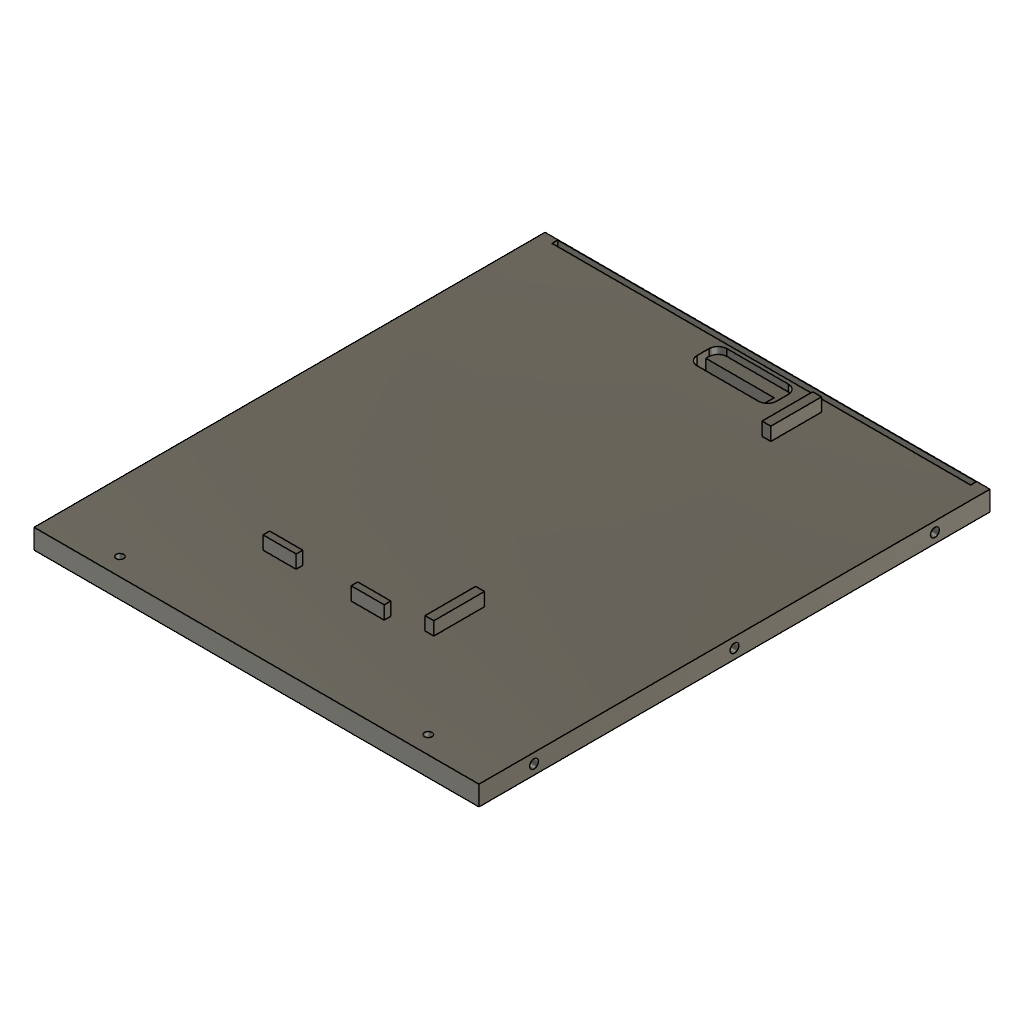
Base (Autodesk Fusion 360 design; units mm, degrees)
part number: 2026-10-19-10-28-36-439
Autodesk Fusion 360 part; units mm, degrees
sketch "plate" plane through (0, 0, 0) normal (0, 0, 1) x (1, 0, 0)
  line L0 (-101, 0) -> (101, 0)
  line L1 (101, 0) -> (101, 232)
  line L2 (101, 232) -> (-101, 232)
  line L3 (-101, 232) -> (-101, 0)
extrude "plate (1)" add sketch "plate" along normal blind 3 from surface at 6
sketch "rib_L" plane through (0, 0, 0) normal (0, 0, 1) x (1, 0, 0)
  line L0 (-101, 0) -> (-91, 0)
  line L1 (-91, 0) -> (-91, 232)
  line L2 (-91, 232) -> (-101, 232)
  line L3 (-101, 232) -> (-101, 0)
extrude "rib_L (1)" add sketch "rib_L" along normal blind 6
sketch "rib_R" plane through (0, 0, 0) normal (0, 0, 1) x (1, 0, 0)
  line L0 (91, 0) -> (101, 0)
  line L1 (101, 0) -> (101, 232)
  line L2 (101, 232) -> (91, 232)
  line L3 (91, 232) -> (91, 0)
extrude "rib_R (1)" add sketch "rib_R" along normal blind 6
sketch "rib_front" plane through (0, 0, 0) normal (0, 0, 1) x (1, 0, 0)
  line L0 (-101, 0) -> (101, 0)
  line L1 (101, 0) -> (101, 14)
  line L2 (101, 14) -> (-101, 14)
  line L3 (-101, 14) -> (-101, 0)
extrude "rib_front (1)" add sketch "rib_front" along normal blind 6
sketch "rib_back" plane through (0, 0, 0) normal (0, 0, 1) x (1, 0, 0)
  line L0 (-101, 222) -> (101, 222)
  line L1 (101, 222) -> (101, 232)
  line L2 (101, 232) -> (-101, 232)
  line L3 (-101, 232) -> (-101, 222)
extrude "rib_back (1)" add sketch "rib_back" along normal blind 6
sketch "rib_long" plane through (0, 0, 0) normal (0, 0, 1) x (1, 0, 0)
  line L0 (-47, 0) -> (-43, 0)
  line L1 (-43, 0) -> (-43, 232)
  line L2 (-43, 232) -> (-47, 232)
  line L3 (-47, 232) -> (-47, 0)
extrude "rib_long (1)" add sketch "rib_long" along normal blind 6
sketch "rib_long (1)" plane through (0, 0, 0) normal (0, 0, 1) x (1, 0, 0)
  line L0 (13, 0) -> (17, 0)
  line L1 (17, 0) -> (17, 232)
  line L2 (17, 232) -> (13, 232)
  line L3 (13, 232) -> (13, 0)
extrude "rib_long (2)" add sketch "rib_long (1)" along normal blind 6
sketch "rib_cross" plane through (0, 0, 0) normal (0, 0, 1) x (1, 0, 0)
  line L0 (-101, 134) -> (101, 134)
  line L1 (101, 134) -> (101, 138)
  line L2 (101, 138) -> (-101, 138)
  line L3 (-101, 138) -> (-101, 134)
extrude "rib_cross (1)" add sketch "rib_cross" along normal blind 6
sketch "pr_guide" plane through (0, 0, 0) normal (0, 0, 1) x (1, 0, 0)
  line L0 (28.5, 48) -> (32.5, 48)
  line L1 (32.5, 48) -> (32.5, 71)
  line L2 (32.5, 71) -> (28.5, 71)
  line L3 (28.5, 71) -> (28.5, 48)
extrude "pr_guide (1)" add sketch "pr_guide" along normal blind 6 from surface at 9
sketch "pr_guide (1)" plane through (0, 0, 0) normal (0, 0, 1) x (1, 0, 0)
  line L0 (28.5, 201) -> (32.5, 201)
  line L1 (32.5, 201) -> (32.5, 224)
  line L2 (32.5, 224) -> (28.5, 224)
  line L3 (28.5, 224) -> (28.5, 201)
extrude "pr_guide (2)" add sketch "pr_guide (1)" along normal blind 6 from surface at 9
sketch "pr_stop" plane through (0, 0, 0) normal (0, 0, 1) x (1, 0, 0)
  line L0 (-40, 43) -> (-25, 43)
  line L1 (-25, 43) -> (-25, 46)
  line L2 (-25, 46) -> (-40, 46)
  line L3 (-40, 46) -> (-40, 43)
extrude "pr_stop (1)" add sketch "pr_stop" along normal blind 6 from surface at 9
sketch "pr_stop (1)" plane through (0, 0, 0) normal (0, 0, 1) x (1, 0, 0)
  line L0 (0, 43) -> (15, 43)
  line L1 (15, 43) -> (15, 46)
  line L2 (15, 46) -> (0, 46)
  line L3 (0, 46) -> (0, 43)
extrude "pr_stop (2)" add sketch "pr_stop (1)" along normal blind 6 from surface at 9
sketch "ins_side_R" plane through (0, 0, 0) normal (1, 0, 0) x (0, 0, -1)
  circle A0 centre (-4.5, 25) radius 2
  circle A1 centre (-4.5, 116) radius 2
  circle A2 centre (-4.5, 207) radius 2
extrude "ins_side_R (1)" cut sketch "ins_side_R" against normal blind 6.2 from surface at 101.2
sketch "ins_side_L" plane through (0, 0, 0) normal (1, 0, 0) x (0, 0, -1)
  circle A0 centre (-4.5, 25) radius 2
  circle A1 centre (-4.5, 116) radius 2
  circle A2 centre (-4.5, 207) radius 2
extrude "ins_side_L (1)" cut sketch "ins_side_L" along normal blind 6.2 from surface at -101.2
sketch "bezel_screw_hole" plane through (0, 0, 0) normal (0, 0, 1) x (1, 0, 0)
  circle A0 centre (-70, 8) radius 1.7
  circle A1 centre (70, 8) radius 1.7
extrude "bezel_screw_hole (1)" cut sketch "bezel_screw_hole" along normal blind 10 from surface at -0.5
sketch "bezel_screw_cone" plane through (0, 0, 0) normal (0, 0, 1) x (1, 0, 0)
  circle A0 centre (-70, 8) radius 3.8
  circle A1 centre (70, 8) radius 3.8
extrude "bezel_screw_cone (1)" cut sketch "bezel_screw_cone" along normal blind 2.1 draft -45 from surface at -0.5
sketch "door_groove" plane through (0, 0, 0) normal (0, 0, 1) x (1, 0, 0)
  line L0 (-95, 229.2) -> (95, 229.2)
  line L1 (95, 229.2) -> (95, 231.8)
  line L2 (95, 231.8) -> (-95, 231.8)
  line L3 (-95, 231.8) -> (-95, 229.2)
extrude "door_groove (1)" cut sketch "door_groove" along normal blind 4.1 from surface at 5
sketch "finger_slot" plane through (0, 0, 0) normal (0, 0, 1) x (1, 0, 0)
  line L0 (-14, 214) -> (14, 214)
  arc A0 (14, 214) -> (18, 218) centre (14, 218) ccw
  line L1 (18, 218) -> (18, 223.5)
  arc A1 (18, 223.5) -> (14, 227.5) centre (14, 223.5) ccw
  line L2 (14, 227.5) -> (-14, 227.5)
  arc A2 (-14, 227.5) -> (-18, 223.5) centre (-14, 223.5) ccw
  line L3 (-18, 223.5) -> (-18, 218)
  arc A3 (-18, 218) -> (-14, 214) centre (-14, 218) ccw
extrude "finger_slot (1)" cut sketch "finger_slot" along normal blind 3.2 from surface at 5.9
extrude "Extrude19" add 6 faces at (-76.3333, 194, 6) (-61.6667, 54, 6) (-24.3333, 94, 6) (-14.6667, 163.3333, 6) (66.3333, 191.7847, 6) (41.6667, 94, 6) along direction (0, 0, -1) blind 6
equation "d62 = -( 6.20 mm )"
named bodies: "Base"
